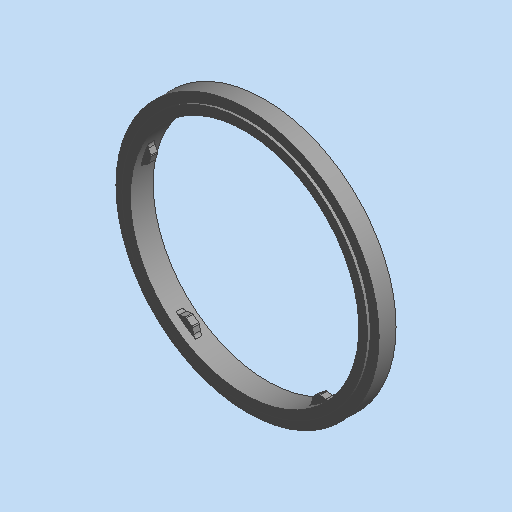
# Autodesk Inventor part: 34638__20211027
Saved by Autodesk Inventor 2023.3 (Build 273359000, 359)
## iProperties
Category: PARTsolutions
Company: FESTO
Part Number: 34638__20211027
Material: Generisch
Catalog Web Link: www.cadenas.de
Description: =<RBPARTNOTITLE2>
Vendor: Festo
Document SubType Name: Modeling
Designer: partserver
Manufacturer: FESTO
Mass: 2 g
Surface Area: 8.7669 cm^2
Volume: 0.440708 cm^3
Density: 1 g/cm^3
Appearance: PSOLRGB-175-175-175
PSOL_IDENT_0: {$CADENAS_DATA\23d-libs\festo\parts\o\ol\ol.prj},160 {VTYP=3D},{NB=34638 OL-3/4},{LINA=34638 OL-3/4}
PSOL_IDENT_1: ,{NN=OL},{DATE=13.10.2021 07:12:24},{GEOMDATE=13.10.2021 07:12:19},{VERSION=},{LINEID=60},{WBVAR=},{
PSOL_IDENT_2: WBNUMERIC=}  {NB=34638 OL-3/4},{LINA=34638 OL-3/4},{KT=DUMMY},{TNR=34638},{TYP=OL-3/4},{INFO=},{ND=G
PSOL_IDENT_3: 3/4},{D1=27.000},{D2=31.100},{D3=29.000},{D4=0.000},{D5=25.550},{H1=2.700},{H2=2.000},{H=0.800},{H3=
PSOL_IDENT_4: 0.300},{H4=1.000},{W=90.000},{R=0.500},{VERS=2},{VN=5},{CNSMASSEXACT=0.002},{EOLDATE=}
NB: 34638 OL-3/4
NN: OL
NT: sealing ring
NBSYN: $TNR. $TYP.
LINA: 34638 OL-3/4
CATALOG: Festo
TNR: 34638
TYP: OL-3/4
D1: 27
D2: 31.1
D3: 29
D4: 0
H1: 2.7
H2: 2
VN: 5
CNSMASSEXACT: 0.002
SUPPLIER: FESTO
ARTICLENO: 34638 OL-3/4
BOMINFO: 34638 OL-3/4
CREATOR: CADENAS GmbH
RBPARTMADEOF: 34638
RBDRAWINGMISSINGSPEC: --
AnP_Kategorie: 2
RBPARTNOTITLE2: Dichtring OL-3/4
RBGBREMARKSINDEX: E
RBSURFACE: --
RBPARTNOTITLE1: Sealing ring OL-3/4
RBSURFACE2: --
AnP_Material: =<Material>
RBMATERIAL: --
RBMATNO: =<Part Number>
RBPARTNO: SIEHE MNR
Title: 34638 OL-3/4
Author: Cadenas PARTsolutions
Comments: =<RBSURFACE2>
Keywords: =<RBPARTMADEOF>
Revision Number: 01
Autodesk Inventor part; units mm, degrees
sketch "Skizze_1" plane through (0, 0, 0) normal (0, 0, 1) x (1, 0, 0)
  line L0 (0, 0) -> (0, 2.7)
  line L1 (13.5, 2.7) -> (13.5, 0)
  line L2 (13.5, 0) -> (14.5, 0)
  line L3 (14.5, 0) -> (14.5, 0.35)
  line L4 (14.5, 0.35) -> (15.55, 0.35)
  line L5 (15.55, 0.35) -> (15.55, 2.35)
  line L6 (15.55, 2.35) -> (14.5, 2.35)
  line L7 (14.5, 2.35) -> (14.5, 2.7)
  line L8 (14.5, 2.7) -> (13.5, 2.7)
  constraints: 18 end point
revolve "Revolution1" add sketch "Skizze_1" angle 360 about axis through (0, 0, 0) along (0, -1, 0)
sketch "Sketch_2" plane through (0, 1.35, 0) normal (0, 1, 0) x (1, 0, 0)
  circle A0 centre (0, 0) radius 14.3
  arc A1 (-13.2073, 2.7959) -> (-9.0415, -10.025) centre (0, 0) ccw
  arc A2 (-9.0415, -10.025) -> (-8.6285, -10.1475) centre (-8.7067, -9.6537) ccw
  line L0 (-8.6285, -10.1475) -> (-7.9937, -10.047)
  arc A3 (-7.8397, -10.0866) -> (-7.9937, -10.047) centre (-7.9624, -10.2445) ccw
  arc A4 (-7.8397, -10.0866) -> (-7.1704, -10.5729) centre (0, 0) ccw
  arc A5 (-7.0851, -10.7072) -> (-7.1704, -10.5729) centre (-7.2826, -10.7384) ccw
  line L1 (-7.0851, -10.7072) -> (-6.9845, -11.3419)
  arc A6 (-6.9845, -11.3419) -> (-6.7403, -11.6969) centre (-6.4907, -11.2637) ccw
  arc A7 (-6.7403, -11.6969) -> (6.7403, -11.6969) centre (0, 0) ccw
  arc A8 (6.7403, -11.6969) -> (6.9845, -11.3419) centre (6.4907, -11.2637) ccw
  line L2 (6.9845, -11.3419) -> (7.0851, -10.7072)
  arc A9 (7.1704, -10.5729) -> (7.0851, -10.7072) centre (7.2826, -10.7384) ccw
  arc A10 (7.1704, -10.5729) -> (7.8397, -10.0866) centre (0, 0) ccw
  arc A11 (7.9937, -10.047) -> (7.8397, -10.0866) centre (7.9624, -10.2445) ccw
  line L3 (7.9937, -10.047) -> (8.6285, -10.1475)
  arc A12 (8.6285, -10.1475) -> (9.0415, -10.025) centre (8.7067, -9.6537) ccw
  arc A13 (9.0415, -10.025) -> (13.2073, 2.7959) centre (0, 0) ccw
  arc A14 (13.2073, 2.7959) -> (12.9451, 3.1378) centre (12.7181, 2.6923) ccw
  line L4 (12.9451, 3.1378) -> (12.3725, 3.4296)
  arc A15 (12.2712, 3.5522) -> (12.3725, 3.4296) centre (12.4633, 3.6078) ccw
  arc A16 (12.2712, 3.5522) -> (12.0155, 4.339) centre (0, 0) ccw
  arc A17 (12.0255, 4.4978) -> (12.0155, 4.339) centre (12.2037, 4.407) ccw
  line L5 (12.0255, 4.4978) -> (12.3172, 5.0704)
  arc A18 (12.3172, 5.0704) -> (12.3283, 5.5011) centre (11.8717, 5.2974) ccw
  arc A19 (12.3283, 5.5011) -> (1.4222, 13.4249) centre (0, 0) ccw
  arc A20 (1.4222, 13.4249) -> (1.016, 13.2812) centre (1.3696, 12.9277) ccw
  line L6 (1.016, 13.2812) -> (0.5616, 12.8268)
  arc A21 (0.4137, 12.7683) -> (0.5616, 12.8268) centre (0.4201, 12.9682) ccw
  arc A22 (0.4137, 12.7683) -> (-0.4137, 12.7683) centre (0, 0) ccw
  arc A23 (-0.5616, 12.8268) -> (-0.4137, 12.7683) centre (-0.4201, 12.9682) ccw
  line L7 (-0.5616, 12.8268) -> (-1.016, 13.2812)
  arc A24 (-1.016, 13.2812) -> (-1.4222, 13.4249) centre (-1.3696, 12.9277) ccw
  arc A25 (-1.4222, 13.4249) -> (-12.3283, 5.5011) centre (0, 0) ccw
  arc A26 (-12.3283, 5.5011) -> (-12.3172, 5.0704) centre (-11.8717, 5.2974) ccw
  line L8 (-12.3172, 5.0704) -> (-12.0255, 4.4978)
  arc A27 (-12.0155, 4.339) -> (-12.0255, 4.4978) centre (-12.2037, 4.407) ccw
  arc A28 (-12.0155, 4.339) -> (-12.2712, 3.5522) centre (0, 0) ccw
  arc A29 (-12.3725, 3.4296) -> (-12.2712, 3.5522) centre (-12.4633, 3.6078) ccw
  line L9 (-12.3725, 3.4296) -> (-12.9451, 3.1378)
  arc A30 (-12.9451, 3.1378) -> (-13.2073, 2.7959) centre (-12.7181, 2.6923) ccw
  constraints: 60 point on circle, 31 centre point, 20 end point
extrude "Extrusion1" add sketch "Sketch_2" along normal mid plane 0.8
ref_plane "ANBAU_XY" through (0, 0, 0) normal (0, 1, 0) x (1, 0, 0)
ref_plane "ANBAU_YZ" through (0, 0, 0) normal (1, 0, 0) x (0, 0, -1)
ref_plane "ANBAU_ZX" through (0, 0, 0) normal (0, 0, -1) x (0, 1, 0)
ref_plane "IP_XY" through (0, 2.7, 0) normal (0, 1, 0) x (1, 0, 0)
ref_plane "IP_YZ" through (0, 2.7, 0) normal (1, 0, 0) x (0, 0, -1)
ref_plane "IP_ZX" through (0, 2.7, 0) normal (0, 0, -1) x (0, 1, 0)
body "Solid1"
